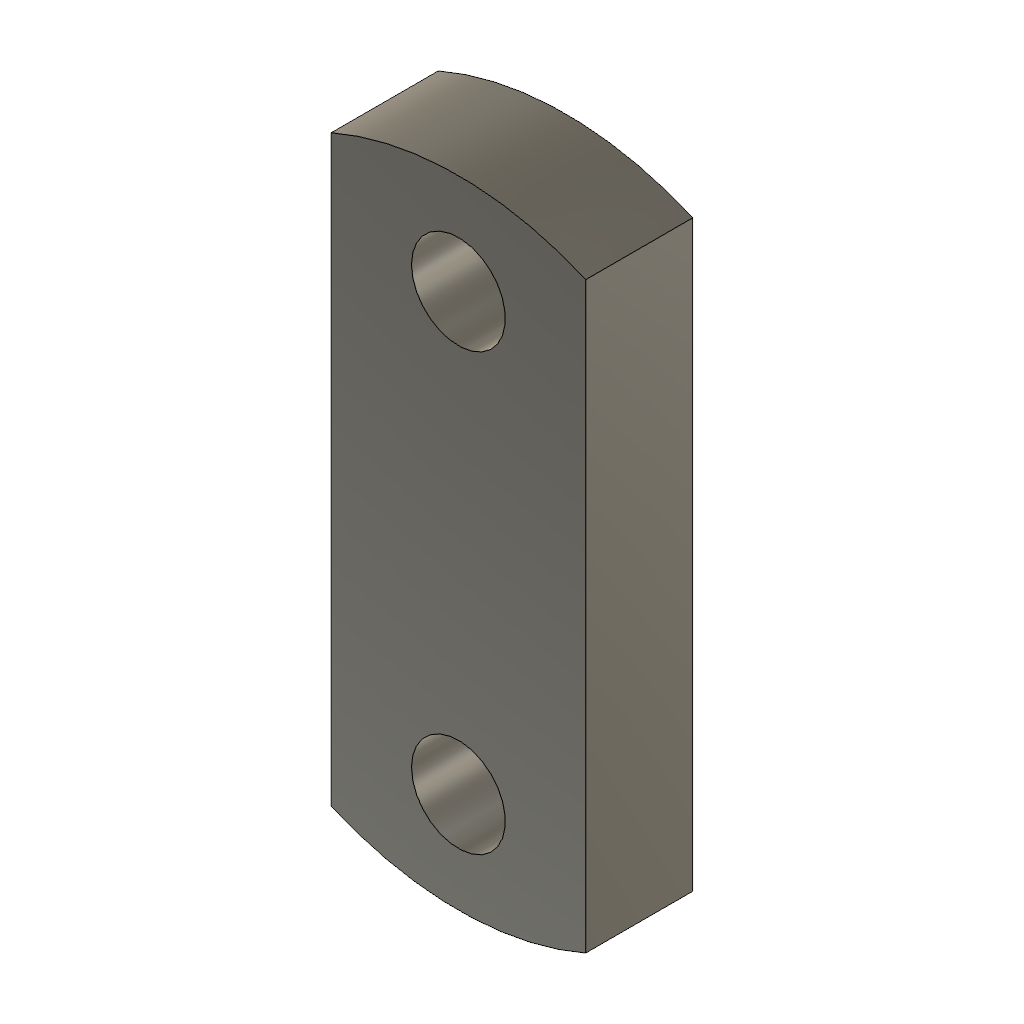
coverplate (Autodesk Fusion 360 design; units mm, degrees)
part number: 2026-10-08-13-52-12-406
Autodesk Fusion 360 part; units mm, degrees
sketch "Sketch1" plane through (0, 0, 0) normal (0, 1, 0) x (1, 0, 0)
  line L0 (0, 0) -> (76, 0)
  line L1 (76, 0) -> (76, -190)
  line L2 (76, -190) -> (0, -190)
  line L3 (0, -190) -> (0, 0)
  dimension "d1" = 76
  dimension "d2" = 190
  constraint horizontal L0
  constraint vertical L1
  constraint horizontal L2
  constraint vertical L3
  constraint coincident L0.start L3.end
  measures "d1" distance of L0.start L0.end
  measures "d2" distance of L0.start L2.end
extrude "Extrude1" add sketch "Sketch1" along normal blind 32
sketch "Sketch2" plane through (0, 0, 0) normal (0, -1, 0) x (1, 0, 0)
  line L0 (76, 190) -> (0, 190)
  line L1 (0, 190) -> (0, 0)
  line L2 (0, 0) -> (76, 0)
  line L3 (76, 0) -> (76, 190)
  line L4 (0, 190) -> (38, 190)
  line L5 (38, 190) -> (38, 160)
  line L6 (38, 160) -> (0, 160)
  line L7 (0, 160) -> (0, 190)
  circle A0 centre (38, 160) radius 14
  line L8 (38, 160) -> (38, 30)
  circle A1 centre (38, 30) radius 14
  dimension "d5" = 38
  dimension "d6" = 30
  dimension "d7" = 28
  dimension "d8" = 130
  dimension "d9" = 28
  constraint horizontal L4
  constraint vertical L5
  constraint horizontal L6
  constraint vertical L7
  constraint coincident L0.end L1.start
  constraint coincident L5.end L6.start
  constraint perpendicular L6 L8
  constraint coincident L8.end A1.centre
  measures "d5" distance of L0.end L4.end
  measures "d6" distance of L0.end L6.end
  measures "d7" diameter of A0
  measures "d8" distance of L5.end L8.end
  measures "d9" diameter of A1
extrude "Extrude2" cut sketch "Sketch2" against normal blind 250 contours L5 A0 L8 | L5 L6 A0 | L6 A0 L8 | A1
sketch "Sketch3" plane through (0, 0, 0) normal (0, -1, 0) x (1, 0, 0)
  circle A0 centre (38, 160) radius 14
  circle A1 centre (38, 30) radius 14
  line L0 (76, 190) -> (0, 190)
  line L1 (0, 190) -> (0, 0)
  line L2 (0, 0) -> (76, 0)
  line L3 (76, 0) -> (76, 190)
  line L4 (0, 190) -> (38, 190)
  line L5 (38, 190) -> (38, 95)
  line L6 (38, 95) -> (0, 95)
  line L7 (0, 95) -> (0, 190)
  circle A2 centre (38, 95) radius 95
  dimension "d12" = 38
  dimension "d13" = 95
  dimension "d14" = 190
  constraint horizontal L4
  constraint vertical L5
  constraint horizontal L6
  constraint vertical L7
  constraint coincident L0.end L1.start
  constraint coincident L5.end L6.start
  measures "d12" distance of L0.end L4.end
  measures "d13" distance of L0.end L6.end
  measures "d14" diameter of A2
extrude "Extrude3" cut sketch "Sketch3" against normal blind 220 contours L0 L1 L4 L7 A2 | L0 L3 A2 | L2 L3 A2 | L1 L2 A2
